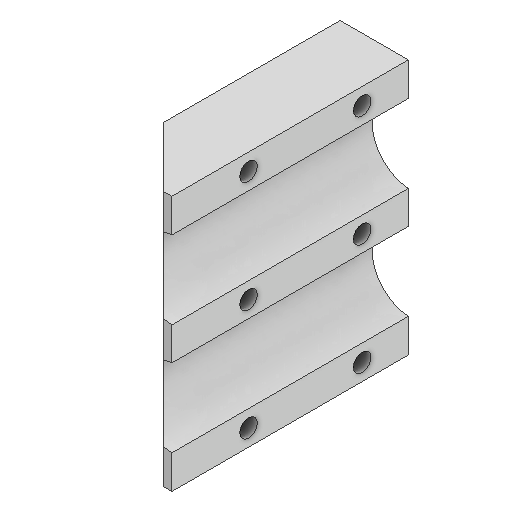
# Autodesk Inventor part: 3DP_PLA_Fiberglass_Pipe_Corner_Bracket_Clamp
Saved by Autodesk Inventor 2027 (Build 310192060, 192F)
## iProperties
Created: 2026-01-07
Part Number: 3DP_PLA_Fiberglass_Pipe_Corner_Bracket_Clamp
Material: Generic
Document SubType Name: Modeling
Designer: User
Density: 1 g/cm^3
Appearance: Default
Author: User
Autodesk Inventor part; units mm, degrees
ref_plane "YZ Plane" through (0, 0, 0) normal (1, 0, 0) x (0, 1, 0)
ref_plane "XZ Plane" through (0, 0, 0) normal (0, 1, 0) x (-1, 0, 0)
ref_plane "XY Plane" through (0, 0, 0) normal (0, 0, 1) x (1, 0, 0)
sketch "Sketch1" plane through (0, 0, 0) normal (0, 1, 0) x (-1, 0, 0)
  line L0 (0, 0) -> (100, 0)
  line L1 (0, 0) -> (0, 100)
  line L2 (100, 0) -> (0, 100)
  dimension "d0" = 100
  dimension "d1" = 100
  constraints: 6 end point
  measures "d0" distance of L0.start L1.end
  measures "d1" distance of L0.start L0.end
extrude "Extrusion1" add sketch "Sketch1" along normal blind 90
sketch "Sketch3" plane through (0, 90, 0) normal (0, 0, -1) x (-1, 0, 0)
  circle A0 centre (-1, -25.5) radius 13.75
  circle A1 centre (-1, -64.5) radius 13.75
  line L0 (0, -90) -> (0, 0) projected
  line L1 (0, 0) -> (100, 0) projected
  dimension "d11" = 90
  dimension "d12" = 27.5
  dimension "d13" = 27.5
  dimension "d14" = 39
  dimension "d63" = 1
  dimension "d64" = 1
  dimension "d65" = 25.5
  constraints: 2 centre point
  measures "d11" distance of L0.start L0.end
  measures "d12" diameter of A0
  measures "d13" diameter of A1
  measures "d14" distance of A1.centre A0.centre
  measures "d63" distance from line of L0 A0.centre
  measures "d64" distance from line of L0 A1.centre
  measures "d65" distance from line of L1 A0.centre
extrude "Extrusion3" cut sketch "Sketch3" against normal through all
sketch "Sketch4" plane through (0, 90, 0) normal (0, 1, 0) x (1, 0, 0)
  line L0 (-100, 0) -> (0, -100) projected
  line L1 (0, -100) -> (0, 0) projected
  line L2 (0, 0) -> (-100, 0) projected
  line L3 (-20, -80) -> (-20, -20)
  line L4 (-20, -20) -> (-80, -20)
  dimension "d18" = 20
  dimension "d19" = 20
  constraints: 4 end point, 2 point on line, 1 perpendicular, 1 vertical
  measures "d18" distance between parallel lines of L1 L3
  measures "d19" distance between parallel lines of L2 L4
extrude "Extrusion4" cut sketch "Sketch4" against normal blind 90 contours L4 L3 L0
sketch "Sketch6" plane through (-20, 90, 20) normal (-1, 0, 0) x (0, 0, 1)
  line L0 (80, -11.7864) -> (-20, -11.7864) projected
  line L1 (-20, -39.2136) -> (80, -39.2136) projected
  line L2 (80, -50.7864) -> (-20, -50.7864) projected
  line L3 (-20, -78.2136) -> (80, -78.2136) projected
  line L4 (60, -90) -> (0, -90) projected
  line L5 (60, 0) -> (60, -90) projected
  line L6 (0, -90) -> (0, 0) projected
  line L7 (0, 0) -> (60, 0) projected
  point P0 (-20, -90)
  point P1 (76, -11.7864)
  point P2 (76, -39.2136)
  point P3 (76, -50.7864)
  point P4 (76, -78.2136)
  point P5 (50, -84.125)
  point P6 (10, -84.125)
  point P7 (50, -45)
  point P8 (10, -45)
  point P9 (50, -5.875)
  point P10 (10, -5.875)
  dimension "d29" = 11.7864
  dimension "d32" = 5.875
  dimension "d34" = 11.5728
  dimension "d60" = 10
  dimension "d61" = 10
  dimension "d62" = 5.875
  dimension "d68" = 45
  constraints: 4 vertical alignment, 3 horizontal alignment
  measures "d29" distance between parallel lines of L4 L3
  measures "d32" distance from line of L4 point (50, -84.125)
  measures "d34" distance between parallel lines of L2 L1
  measures "d60" distance from line of L5 point (50, -84.125)
  measures "d61" distance from line of L6 point (10, -84.125)
  measures "d62" distance from line of L7 point (50, -5.875)
  measures "d68" distance from line of L4 point (50, -45)
hole "Hole1" at (-20, 5.875, 70) at (-20, 5.875, 30) at (-20, 45, 70) at (-20, 45, 30) at (-20, 84.125, 70) at (-20, 84.125, 30) direction (1, 0, 0) diameter 6.2 end through all
sketch "Sketch8" plane through (0, 78.2136, 0) normal (0, 0, -1) x (-1, 0, 0)
  line L0 (105, 34) -> (-10, 34)
  line L1 (-10, 34) -> (-10, -90)
  line L2 (-10, -90) -> (105, -90)
  line L3 (105, -90) -> (105, 34)
  point P0 (0, -78.2136)
  constraints: 8 end point, 2 parallel, 1 horizontal, 1 perpendicular
extrude "Extrusion6" cut sketch "Sketch8" against normal up to surface (20 mm away)
sketch "Sketch9" plane through (0, 0, 20) normal (0, 0, -1) x (-1, 0, 0)
  line L0 (0, 78.2136) -> (0, 90) projected
  arc A0 (0, 50.7864) -> (0, 78.2136) centre (-1, 64.5) ccw projected
  line L1 (0, 39.2136) -> (0, 50.7864) projected
  arc A1 (0, 11.7864) -> (0, 39.2136) centre (-1, 25.5) ccw projected
  line L2 (0, 0) -> (0, 11.7864) projected
  line L3 (20, 0) -> (0, 0) projected
  line L4 (20, 90) -> (20, 0) projected
  line L5 (0, 90) -> (20, 90) projected
  point P0 (0, 0)
extrude "Extrusion7" add sketch "Sketch9" along normal blind 6.25
sketch "Sketch10" plane through (-20, 0, 80) normal (-1, 0, 0) x (0, 0, 1)
  circle A0 centre (-50, 84.125) radius 3.1 projected
  circle A1 centre (-10, 84.125) radius 3.1 projected
  circle A2 centre (-50, 45) radius 3.1 projected
  circle A3 centre (-10, 45) radius 3.1 projected
  circle A4 centre (-50, 5.875) radius 3.1 projected
  circle A5 centre (-10, 5.875) radius 3.1 projected
  line L0 (-66.25, 90) -> (0, 90) projected
  line L1 (-66.25, 0) -> (-66.25, 90) projected
  line L2 (0, 0) -> (-66.25, 0) projected
  line L3 (0, 90) -> (0, 0) projected
  point P0 (-80, 0)
extrude "Extrusion8" add sketch "Sketch10" along normal blind 4
chamfer "Chamfer2" distance 4 angle 45 1 edges at (-24, 45, 80)
sketch "Sketch11" plane through (0, 0, 0) normal (0, -1, 0) x (1, 0, 0)
  line L0 (9, 97) -> (-33, 97)
  line L1 (-33, 97) -> (-33, 4)
  line L2 (-33, 4) -> (9, 4)
  line L3 (9, 4) -> (9, 97)
  line L4 (-24, 76) -> (0, 100) projected
  line L5 (-24, 13.75) -> (-24, 76) projected
  line L6 (0, 13.75) -> (-24, 13.75) projected
  line L7 (0, 100) -> (0, 13.75) projected
  point P0 (0, 0)
  dimension "d74" = 3
  constraints: 8 end point, 2 parallel, 1 horizontal, 1 perpendicular
  measures "d74" distance from line of L0 L4.end
extrude "Extrusion9" cut sketch "Sketch11" against normal through all contours L3 L2 L1 L0 L4 L5 L6 L7 | L7 L6 L5 L4 L0 keep common part
equation "\"d0\" = d1"
equation "\"d64\" = d63"
equation "\"d19\" = d18"
body "Solid1"
